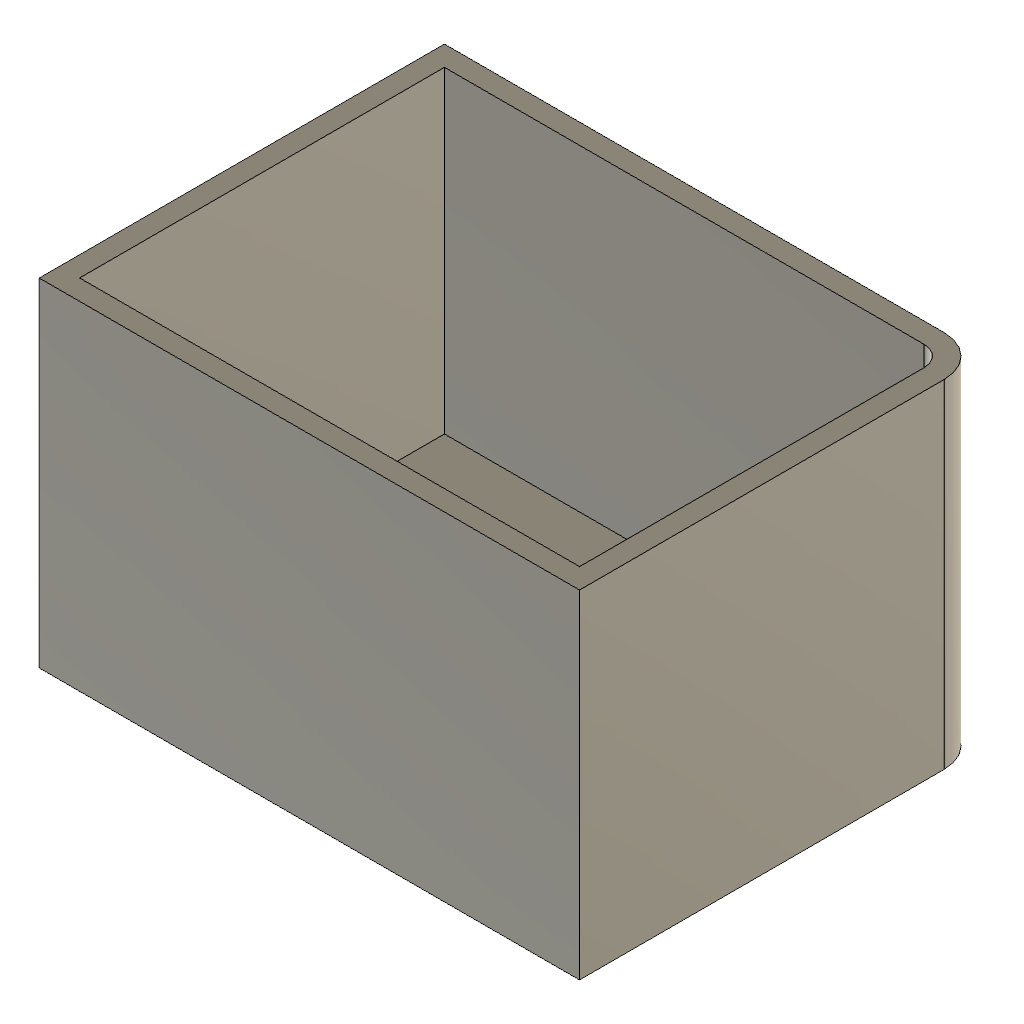
vendor_FilletShell (Autodesk Fusion 360 design; units mm, degrees)
Autodesk Fusion 360 part; units mm, degrees
sketch "Base Sketch" plane through (0, 0, 0) normal (0, 0, 1) x (1, 0, 0)
  line L0 (0, 0) -> (40, 0)
  line L1 (40, 0) -> (40, 30)
  line L2 (40, 30) -> (0, 30)
  line L3 (0, 30) -> (0, 0)
extrude "Base Extrude" add sketch "Base Sketch" along normal blind 25
fillet "Fillet" radius 3 1 edges at (40, 30, 12.5)
shell "Shell" thickness 1.5 removed faces 1 at (25.6667, 10, 25)
equation "height = 20.0 mm"
